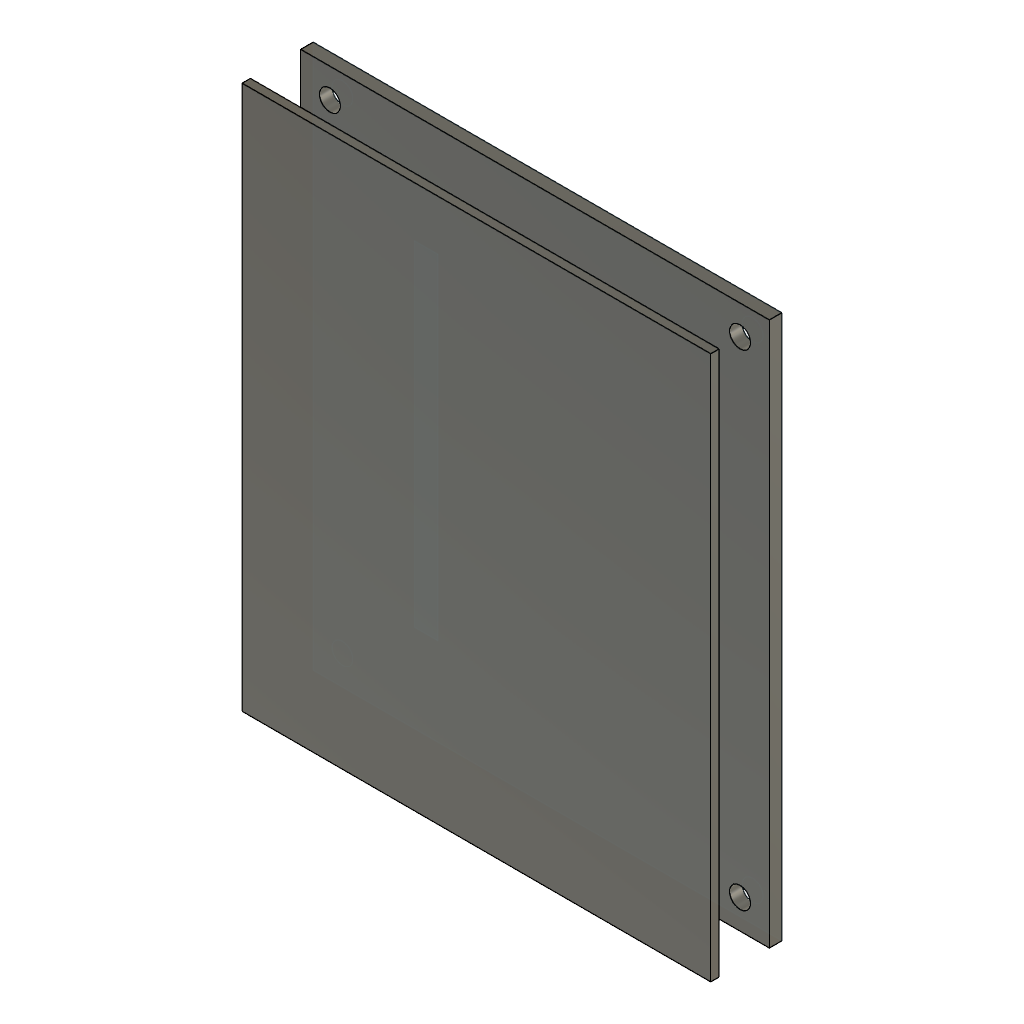
rasp_supporter (Autodesk Fusion 360 design; units mm, degrees)
part number: 2026-10-29-23-16-48-032
Autodesk Fusion 360 part; units mm, degrees
sketch "Schizzo1" plane through (0, 0, 0) normal (0, 1, 0) x (1, 0, 0)
  line L0 (0, 0) -> (55, 0)
  line L1 (55, 0) -> (55, 76.5)
  line L2 (55, 76.5) -> (0, 76.5)
  line L3 (0, 76.5) -> (0, 0)
  line L4 (0, 0) -> (27.5, 0)
  line L5 (27.5, 0) -> (29, 0)
  line L6 (26, 0) -> (26, 76.5)
  line L7 (26, 0) -> (24.5, 0)
  line L8 (24.5, 0) -> (24.5, 76.5)
  line L9 (26, 0) -> (27.5, 0)
  line L10 (27.5, 0) -> (27.5, 76.5)
  line L11 (27.5, 0) -> (36, 0)
  line L12 (24.5, 0) -> (16, 0)
  line L13 (16, 0) -> (16, 76.5)
  line L14 (36, 0) -> (36, 76.5)
  line L15 (0, 38.25) -> (55, 38.25)
  line L16 (0, 60) -> (55, 60)
  line L17 (0, 20) -> (55, 20)
  line L18 (16, 20) -> (13, 20)
  line L19 (13, 20) -> (13, 60)
  line L20 (13, 60) -> (16, 60)
  line L21 (16, 60) -> (16, 20)
  line L22 (36, 60) -> (39, 60)
  line L23 (39, 60) -> (39, 20.0779)
  line L24 (39, 20.0779) -> (36, 20.0779)
  line L25 (36, 20.0779) -> (36, 60)
  line L26 (-5, 70, 25) -> (60, 70, 25)
  line L27 (60, 70, 25) -> (60, 14, 25)
  line L28 (60, 14, 25) -> (-5, 14, 25)
  line L29 (-5, 14, 25) -> (-5, 70, 25)
  line L30 (-5, 70, 25) -> (-1.5, 70, 25)
  line L31 (-5, 70, 25) -> (-5, 66.5, 25)
  line L32 (-5, 14, 25) -> (-1.5, 14, 25)
  line L33 (-5, 14, 25) -> (-5, 17.5, 25)
  line L34 (60, 14, 25) -> (56.5, 14, 25)
  line L35 (-1.5, 14, 25) -> (-1.5, 70, 25)
  line L36 (-5, 66.5, 25) -> (60, 66.5, 25)
  line L37 (-5, 17.5, 25) -> (60, 17.5, 25)
  line L38 (56.5, 14, 25) -> (56.5, 70, 25)
  circle A0 through (-0.25, 66.5, 25) (-2.125, 67.5825, 25) (-2.125, 65.4175, 25)
  circle A1 through (57.75, 66.5, 25) (55.875, 67.5825, 25) (55.875, 65.4175, 25)
  circle A2 through (-0.25, 17.5, 25) (-2.125, 18.5825, 25) (-2.125, 16.4175, 25)
  circle A3 through (57.75, 17.5, 25) (55.875, 18.5825, 25) (55.875, 16.4175, 25)
  dimension "dog_base_larghezza" = 55
  dimension "dog_base_altezza" = 76.5
  dimension "dog_nervatura_spessore" = 1.5
  dimension "dog_vano_destro" = 8.5
  dimension "dog_vano_sinistro" = 8.5
  dimension "dog_risalto_sinistro" = 3
  dimension "dog_risalto_destro" = 3
  dimension "dog_piastra_larghezza" = 65
  dimension "dog_piastra_altezza" = 56
  dimension "dog_bordo_alto_sinistro" = 3.5
  dimension "dog_bordo_superiore" = 3.5
  dimension "dog_bordo_basso_sinistro" = 3.5
  dimension "dog_bordo_inferiore" = 3.5
  dimension "dog_bordo_basso_destro" = 3.5
  dimension "dog_foro_alto_sinistro" = 2.5
  dimension "dog_foro_alto_destro" = 2.5
  dimension "dog_foro_basso_sinistro" = 2.5
  dimension "dog_foro_basso_destro" = 2.5
  constraint horizontal L0
  constraint vertical L1
  constraint horizontal L2
  constraint vertical L3
  constraint coincident L0.start L3.end
  constraint midpoint L0 L4.end
  constraint coincident L0 L5.end
  constraint coincident L0 L6.start
  constraint coincident L2 L6.end
  constraint perpendicular L2 L6
  constraint perpendicular L6 L7
  constraint coincident L2 L8.end
  constraint perpendicular L2 L8
  constraint midpoint L2 L10.end
  constraint perpendicular L10 L11
  constraint perpendicular L8 L12
  constraint coincident L2 L13.end
  constraint perpendicular L2 L13
  constraint coincident L2 L14.end
  constraint perpendicular L2 L14
  constraint midpoint L3 L15.start
  constraint midpoint L1 L15.end
  constraint coincident L3 L16.start
  constraint coincident L1 L16.end
  constraint perpendicular L1 L16
  constraint coincident L3 L17.start
  constraint coincident L1 L17.end
  constraint perpendicular L1 L17
  constraint horizontal L18
  constraint vertical L19
  constraint horizontal L20
  constraint vertical L21
  constraint coincident L17 L18.start
  constraint coincident L13 L18.start
  constraint horizontal L22
  constraint vertical L23
  constraint horizontal L24
  constraint vertical L25
  constraint coincident L14 L22.start
  constraint coincident L16 L22.start
  measures "dog_base_larghezza" distance of L0.start L0.end
  measures "dog_base_altezza" distance of L0.start L2.end
  measures "dog_nervatura_spessore" distance of L6.start L7.end
  measures "dog_vano_destro" distance of L4.end L11.end
  measures "dog_vano_sinistro" distance of L7.end L12.end
  measures "dog_risalto_sinistro" distance of L18.start L18.end
  measures "dog_risalto_destro" distance of L22.start L22.end
extrude "Estrusione1" add sketch "Schizzo1" along normal blind 1.5 contours L0 L3 L4 L13 L17 L18 | L0 L4 L8 L12 L13 L17 | L3 L15 L17 L19 | L0 L4 L6 L7 L8 L17 | L8 L13 L15 L17 L21 | L3 L15 L16 L19 | L0 L4 L6 L9 L10 L17 | L8 L13 L15 L16 L21 | L2 L3 L13 L16 L20 | L0 L5 L10 L11 L14 L17 | L2 L8 L13 L16 | L10 L14 L15 L17 L25 | L2 L6 L8 L16 | L0 L1 L14 L17 | L10 L14 L15 L16 L25 | L1 L14 L15 L17 L23 L24 | L2 L6 L10 L16 | L2 L10 L14 L16 | L1 L2 L14 L16 L22 | L1 L15 L16 L23 makes body 1
extrude "Estrusione2" add sketch "Schizzo1" along normal blind 10 contours L13 L15 L17 L18 L19 L21 | L6 L8 L15 L17 | L13 L15 L16 L19 L20 L21 | L6 L10 L15 L17 | L6 L8 L15 L16 | L6 L10 L15 L16 | L14 L15 L23 L24 L25 | L14 L15 L16 L22 L23 L25 bodies 1
extrude "Estrusione3" add sketch "Schizzo1" along normal blind 2 separate body contours L26 L29 L30 L31 L35 L36 A0 | L26 L35 L36 L38 A0 A1 | L29 L35 L36 L37 A0 A2 | L26 L27 L36 L38 A1 | L28 L29 L32 L33 L35 L37 A2 | L35 L36 L37 L38 A0 A1 A2 A3 | L27 L36 L37 L38 A1 A3 | L28 L35 L37 L38 A2 A3 | L27 L28 L34 L37 L38 A3 in plane through (0, 25, 0) normal (0, 1, 0) makes body 2
move_body "Sposta1" bodies 2 to x (0, 0, -1) y (0, 1, 0) z (1, 0, 0) at (65, -15, -12)
move_body "Sposta2" bodies 2 to x (1, 0, 0) y (0, 1, 0) z (0, 0, 1) at (4.5, 0, 0)
extrude "Estrusione15" add 1 faces at (55, 0.5, -25.5) along direction (1, 0, 0) blind 0.5 on bodies 1 bodies 1
extrude "Estrusione16" cut 1 faces at (37, 1, 0) along direction (0, 0, -1) blind 7 on bodies 1 bodies 1
extrude "Estrusione17" cut 1 faces at (37, 1, -76.5) along direction (0, 0, 1) blind 4.5 on bodies 1 bodies 1
extrude "Estrusione18" add 1 faces at (0, 0.5, -50.3333) along direction (-1, 0, 0) blind 0.5 on bodies 1 bodies 1
extrude "Estrusione19" cut 1 faces at (50, 1.5, -33.026) along direction (0, -1, 0) blind 0.5 on bodies 1 bodies 1
extrude "Estrusione20" cut 1 faces at (24.5, 7, -33.3333) along direction (1, 0, 0) blind 0.1 on bodies 1 bodies 1
extrude "Estrusione21" cut 1 faces at (27.5, 7, -46.6667) along direction (-1, 0, 0) blind 0.1 on bodies 1 bodies 1
extrude "Estrusione22" cut 1 faces at (16, 4, -33.3333) along direction (-1, 0, 0) blind 0.1 on bodies 1 bodies 1
extrude "Estrusione23" cut 1 faces at (36, 4, -33.3853) along direction (1, 0, 0) blind 0.1 on bodies 1 bodies 1
extrude "Estrusione24" cut 1 faces at (39, 4, -46.6926) along direction (-1, 0, 0) blind 0.1 on bodies 1 bodies 1
extrude "Estrusione25" cut 1 faces at (13, 7, -33.3333) along direction (1, 0, 0) blind 0.1 on bodies 1 bodies 1
extrude "Estrusione26" cut 1 faces at (35.3938, 12, -48.8518) along direction (0, -1, 0) blind 0.5 on bodies 2 bodies 2
extrude "Estrusione27" add 1 faces at (49.9667, 1, -33.026) along direction (0, 1, 0) blind 3 on bodies 1 bodies 1
extrude "Estrusione28" cut 1 faces at (36.8333, 0, -50.3333) along direction (0, 1, 0) blind 3 on bodies 1 bodies 1
sketch "Schizzo2" plane through (0, 10, 0) normal (0, 1, 0) x (0, 0, 1)
  line L0 (-60, 13.1) -> (-20, 13.1)
  line L1 (-20, 13.1) -> (-20, 15.9)
  line L2 (-20, 15.9) -> (-60, 15.9)
  line L3 (-60, 15.9) -> (-60, 13.1)
sketch "Schizzo3" plane through (0, 11.5, 0) normal (0, 1, 0) x (0, 0, -1)
  circle A0 centre (68.5, -3) radius 1.25
  circle A1 centre (10.5, -3) radius 1.25
  circle A2 centre (68.5, -52) radius 1.25
  circle A3 centre (10.5, -52) radius 1.25
  line L0 (7, 0.5) -> (7, -55.5)
  line L1 (7, -55.5) -> (72, -55.5)
  line L2 (72, -55.5) -> (72, 0.5)
  line L3 (72, 0.5) -> (7, 0.5)
extrude "Estrusione4" [suppressed]
extrude "Estrusione5" [suppressed]
extrude "Estrusione6" [suppressed]
extrude "Estrusione7" [suppressed]
extrude "Estrusione8" [suppressed]
fillet "Raccordo3" [suppressed]
extrude "Estrusione9" [suppressed]
extrude "Estrusione10" [suppressed]
extrude "Estrusione11" [suppressed]
extrude "Estrusione12" [suppressed]
extrude "Estrusione13" [suppressed]
extrude "Estrusione14" [suppressed]
fillet "Raccordo4" [suppressed]
fillet "Raccordo5" [suppressed]
equation "dog_base_larghezza = 55 mm" comment "Quota originale mantenuta; nome assegnato durante riordino dello schizzo."
equation "dog_base_altezza = 76.5 mm" comment "Quota originale mantenuta; nome assegnato durante riordino dello schizzo."
equation "dog_nervatura_spessore = 1.5 mm" comment "Quota originale mantenuta; nome assegnato durante riordino dello schizzo."
equation "dog_vano_destro = 8.5 mm" comment "Quota originale mantenuta; nome assegnato durante riordino dello schizzo."
equation "dog_vano_sinistro = 8.5 mm" comment "Quota originale mantenuta; nome assegnato durante riordino dello schizzo."
equation "dog_risalto_sinistro = 3 mm" comment "Quota originale mantenuta; nome assegnato durante riordino dello schizzo."
equation "dog_risalto_destro = 3 mm" comment "Quota originale mantenuta; nome assegnato durante riordino dello schizzo."
equation "dog_piastra_larghezza = 65 mm" comment "Quota originale mantenuta; nome assegnato durante riordino dello schizzo."
equation "dog_piastra_altezza = 56 mm" comment "Quota originale mantenuta; nome assegnato durante riordino dello schizzo."
equation "dog_bordo_alto_sinistro = 3.5 mm" comment "Quota originale mantenuta; nome assegnato durante riordino dello schizzo."
equation "dog_bordo_superiore = 3.5 mm" comment "Quota originale mantenuta; nome assegnato durante riordino dello schizzo."
equation "dog_bordo_basso_sinistro = 3.5 mm" comment "Quota originale mantenuta; nome assegnato durante riordino dello schizzo."
equation "dog_bordo_inferiore = 3.5 mm" comment "Quota originale mantenuta; nome assegnato durante riordino dello schizzo."
equation "dog_bordo_basso_destro = 3.5 mm" comment "Quota originale mantenuta; nome assegnato durante riordino dello schizzo."
equation "dog_foro_alto_sinistro = 2.5 mm" comment "Quota originale mantenuta; nome assegnato durante riordino dello schizzo."
equation "dog_foro_alto_destro = 2.5 mm" comment "Quota originale mantenuta; nome assegnato durante riordino dello schizzo."
equation "dog_foro_basso_sinistro = 2.5 mm" comment "Quota originale mantenuta; nome assegnato durante riordino dello schizzo."
equation "dog_foro_basso_destro = 2.5 mm" comment "Quota originale mantenuta; nome assegnato durante riordino dello schizzo."
